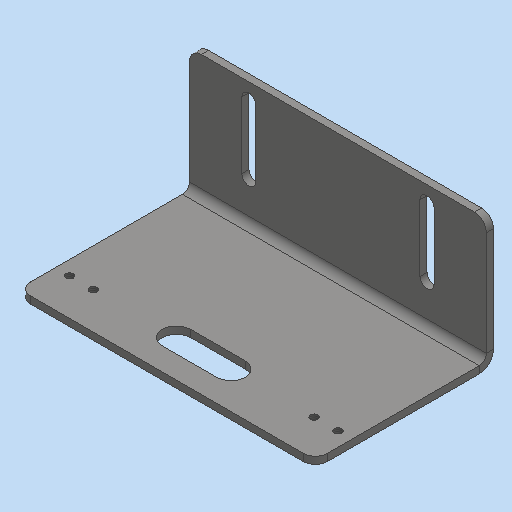
# Autodesk Inventor part: MM0937AN200_G04_138
Saved by Autodesk Inventor 2023.3 (Build 273359000, 359)
## iProperties
Part Number: MM0937AN200_G04_138
Material: 1.4301 X5CrNi18-10
Description: =<RBPARTNOTITLE2>
Document SubType Name: Blech
Designer: Benutzer
Mass: 348.48 g
Surface Area: 318.92 cm^2
Volume: 44.3923 cm^3
Density: 7.85 g/cm^3
Sheet Metal Rule: Standard_mm
Appearance: Stahl - rostfrei AnP
Flat Pattern Width: 12.5 cm
Flat Pattern Length: 12.4786 cm
Flat Pattern Area: 155.982 cm^2
Sheet Metal Width: 125,000 mm
Sheet Metal Length: 124,786 mm
Sheet Metal Area: 15598,230 mm^2
Vendor: ASW
RBCHANGEDESCRIPTION1: Erstfreigabe
RBCHANGENO1: 00
RBDOCUMENTTYPE: DRF
RBDOCUMENTVERSION: 00
RBDRAWINGMAINSCALE: 1:1
RBDRAWINGMISSINGSPEC: --
RBDRAWINGVOLUME: --
RBDSV1: 0850
RBGBDETAILS: 43274
RBGBEDGESIN1: +0,5
RBGBEDGESIN2: +0,2
RBGBEDGESOUT1: -0,3
RBGBEDGESOUT2: -0,1
RBMATERIAL: =<Material>
RBMATMEETS: --
RBMATNO: =<Part Number>
RBORGUNITRESPONSIBLE1: AnP/TEF1
RBPARTMADEOF: 55 x 75 x 125 (FM)
RBPARTNO: SIEHE MNR
RBPARTNOTITLE1: manufactured part
RBPARTNOTITLE2: Anfertigungsteil
RBPARTSAFETYINDICATOR: --
RBSURFACE: --
RBSURFACE2: --
RBZEDGESNORM: ISO13715:2002-06
RBZGENDIMCLASS: m
RBZGENDIMNORM: ISO 2768-1:1989-11
RBZGENGEOCLASS: H
RBZGENGEONORM: ISO 2768-2:1989-11
RBZSURFACENORM: ISO13D2:2002-02
RBZTOLERANCENORM: ISO 14405-1:2010-12
AnP_Material: =<Material>
AnP_TemplVers: 20190222
AnP_Kategorie: 1
MaxAbmaße: 55 x 75 x 125 (FM)
Author: Benutzer
Keywords: =<RBPARTMADEOF>
Comments: =<RBSURFACE2>
Revision Number: 01
Autodesk Inventor part; units mm, degrees
ref_plane "YZ Plane" through (0, 0, 0) normal (1, 0, 0) x (0, 1, 0)
ref_plane "XY Plane" through (0, 0, 0) normal (0, 0, 1) x (1, 0, 0)
sketch "Skizze1" plane through (0, 0, 0) normal (0, 0, 1) x (1, 0, 0)
  line L0 (0, 0) -> (125, 0)
  line L1 (125, 0) -> (125, 72)
  line L2 (125, 72) -> (0, 72)
  line L3 (0, 72) -> (0, 0)
  dimension "d0" = 125
  dimension "d1" = 72
  constraints: 8 end point, 2 parallel, 1 horizontal, 1 perpendicular
  measures "d0" distance of L2.end L1.end
  measures "d1" distance of L1.end L0.end
extrude "Extrusion1" add sketch "Skizze1" along normal blind 3
fillet "Rundung1" radius 5 2 edges at (0, 0, 1.5) (125, 0, 1.5)
sketch "Skizze2" plane through (0, 0, 3) normal (0, 0, 1) x (1, 0, 0)
  line L0 (5, 0) -> (120, 0) projected
  line L1 (125, 5) -> (125, 72) projected
  line L2 (0, 72) -> (0, 5) projected
  line L3 (125, 72) -> (0, 72) projected
  point P0 (0, 0)
  point P1 (16, 15.5)
  point P2 (119, 15.5)
  point P3 (109, 15.5)
  point P4 (6, 15.5)
  dimension "d42" = 56.5
  dimension "d43" = 6
  dimension "d44" = 6
  dimension "d45" = 103
  dimension "d46" = 103
  constraints: 3 horizontal alignment
  measures "d42" distance from line of point (6, 15.5) L3
  measures "d43" distance from line of point (6, 15.5) L2
  measures "d44" distance from line of L1 point (119, 15.5)
  measures "d45" distance of point (109, 15.5) point (6, 15.5)
  measures "d46" distance of point (16, 15.5) point (119, 15.5)
hole "Bohrung1" at (16, 15.5, 3) at (119, 15.5, 3) at (109, 15.5, 3) at (6, 15.5, 3) direction (0, 0, -1) diameter 3.242 end through all thread size "M4x0.7" designation "M4" class "6H" standard "ISO Metric profile"
sketch "Skizze3" plane through (0, 72, 3) normal (0, 1, 0) x (-1, 0, 0)
  line L0 (-125, 0) -> (0, 0)
  line L1 (0, 0) -> (0, 52)
  line L2 (0, 52) -> (-125, 52)
  line L3 (-125, 52) -> (-125, 0)
  constraints: 4 end point, 4 other
edge flange "Lasche1" height 55 angle 90 thickness 3 bend radius 3 thickness toward (0, 1, 0) relief tear relief width 3 relief depth 1.5 edges at (62.5, 72, 3) wall of the first edge with corners at (125, 72, 3) (0, 72, 3) (0, 72, 55) (125, 72, 55)
bend "Biegung1"
corner "Ecke1"
sketch "Skizze4" plane through (0, 75, 55) normal (0, 1, 0) x (1, 0, 0)
  line L0 (125, 49) -> (0, 49) projected
  line L1 (0, 0) -> (0, 49) projected
  line L2 (125, 0) -> (0, 0) projected
  line L3 (125, 49) -> (125, 0) projected
  line L4 (25, 35) -> (25, 7) construction
  line L5 (22, 35) -> (22, 7)
  line L6 (28, 7) -> (28, 35)
  arc A0 (28, 35) -> (22, 35) centre (25, 35) ccw
  arc A1 (22, 7) -> (28, 7) centre (25, 7) ccw
  line L7 (100, 35) -> (100, 7) construction
  line L8 (97, 35) -> (97, 7)
  line L9 (103, 7) -> (103, 35)
  arc A2 (103, 35) -> (97, 35) centre (100, 35) ccw
  arc A3 (97, 7) -> (103, 7) centre (100, 7) ccw
  line L10 (100, 35) -> (128, 35) construction
  point P0 (0, 55)
  point P1 (25, 21)
  point P2 (100, 21)
  dimension "d27" = 28
  dimension "d28" = 6
  dimension "d29" = 28
  dimension "d30" = 90
  dimension "d31" = 6
  dimension "d32" = 25
  dimension "d33" = 25
  dimension "d39" = 21
  constraints: 18 end point, 8 point on circle, 8 tangent, 4 centre point, 3 parallel, 2 midpoint, 1 horizontal, 1 horizontal alignment, 1 perpendicular, 1 vertical
  measures "d27" distance of L4.start L4.end
  measures "d28" diameter of A1
  measures "d29" distance of L7.start L7.end
  measures "d30" angle of L7 L10
  measures "d31" diameter of A3
  measures "d32" distance from line of point (25, 21) L1
  measures "d33" distance from line of L3 point (100, 21)
  measures "d39" distance from line of L2 point (25, 21)
extrude "Extrusion2" cut sketch "Skizze4" against normal through all contours A0 L6 A1 L5 | A2 L9 A3 L8
fillet "Rundung2" radius 5 2 edges at (125, 73.5, 55) (0, 73.5, 55)
ref_plane "Arbeitsebene1" through (0, 75, 0) normal (0, 1, 0) x (-1, 0, 0)
sketch "Skizze5" plane through (0, 0, 0) normal (0, 0, -1) x (-1, 0, 0)
  line L0 (-74, 15.5) -> (-51, 15.5) construction
  line L1 (-74, 9.5) -> (-51, 9.5)
  line L2 (-51, 21.5) -> (-74, 21.5)
  arc A0 (-74, 21.5) -> (-74, 9.5) centre (-74, 15.5) ccw
  arc A1 (-51, 9.5) -> (-51, 21.5) centre (-51, 15.5) ccw
  circle A2 centre (-119, 15.5) radius 1.621 projected
  circle A3 centre (-6, 15.5) radius 1.621 projected
  point P0 (0, 0)
  point P1 (-62.5, 15.5)
  dimension "d47" = 45
  dimension "d48" = 45
  dimension "d51" = 6
  constraints: 8 end point, 4 point on circle, 4 tangent, 2 centre point, 1 horizontal, 1 horizontal alignment, 1 midpoint, 1 parallel
  measures "d47" distance of L0.start A2.centre
  measures "d48" distance of A3.centre L0.end
  measures "d51" radius of A1
extrude "Ausklinkung1" cut sketch "Skizze5" against normal blind 3 contours A0 L2 A1 L1
equation "\"d48\" = d47"
equation "\"d49\" = Stärke"
equation "\"d17\" = BreiteBiegungsfreistellung"
equation "\"d18\" = TiefeBiegungsfreistellung"
equation "\"d19\" = MinimalRest"
equation "\"d20\" = Biegeradius"
equation "\"d23\" = Biegeradius"
equation "\"d24\" = GrößeEckenfreistellung"
equation "\"d25\" = Abstandsgröße"
equation "\"d26\" = JacobiRadiusGröße"
equation "\"d41\" = Stärke"
equation "\"Biegeradius\" = Stärke"
equation "\"BreiteBiegungsfreistellung\" = Stärke"
equation "\"TiefeBiegungsfreistellung\" = 0.5 * Stärke"
equation "\"GrößeEckenfreistellung\" = 4 * Stärke"
equation "\"MinimalRest\" = 2 * Stärke"
equation "\"Übergangsradius\" = Biegeradius"
equation "\"JacobiRadiusGröße\" = Biegeradius"
equation "\"Abstandsgröße\" = Stärke"
equation "\"Stärke\" = 3"
